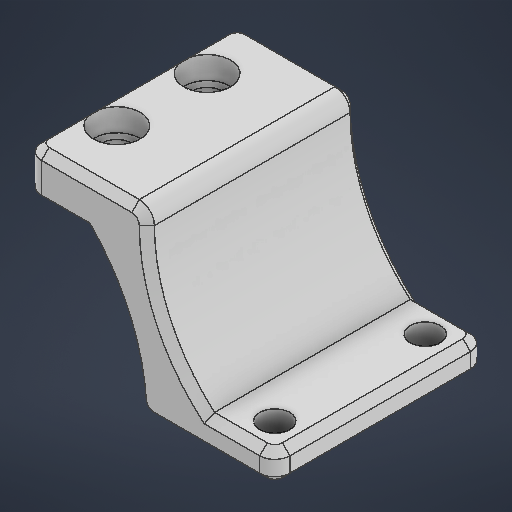
# Autodesk Inventor part: rali-x support
Saved by Autodesk Inventor 2026.2 (Build 302298010, 298A)
## iProperties
Created: 2026-04-26
Part Number: rali-x support
Material: 일반
Document SubType Name: Modeling
Designer: work
Density: 1 g/cm^3
Appearance: 기본값
Author: work
Autodesk Inventor part; units mm, degrees
ref_plane "YZ Plane" through (0, 0, 0) normal (1, 0, 0) x (0, 1, 0)
sketch "스케치1" plane through (0, 0, 0) normal (1, 0, 0) x (0, 1, 0)
  line L0 (0, 0) -> (67.5, 0)
  line L1 (54, 10) -> (54, -10)
  line L2 (67.5, 6) -> (67.5, -6)
  point P0 (54, 0)
  dimension "d0" = 67.5
  dimension "d1" = 54
  dimension "d2" = 20
  dimension "d3" = 12
  constraints: 6 end point, 2 midpoint, 2 vertical, 1 horizontal, 1 point on line
  measures "d0" distance of L0.start L0.end
  measures "d1" distance of L0.start point (54, 0)
  measures "d2" distance of L1.start L1.end
  measures "d3" distance of L2.start L2.end
ref_plane "작업 평면1" through (0, 67.5, 0) normal (0, 1, 0) x (-1, 0, 0)
sketch "스케치2" plane through (0, 67.5, 0) normal (0, 1, 0) x (-1, 0, 0)
  line L0 (0, 6) -> (0, -6) construction
  circle A0 centre (0, 6) radius 2
  circle A1 centre (0, -6) radius 2
  line L1 (4, 10) -> (-12, 10)
  line L2 (-12, 10) -> (-12, -10)
  line L3 (-12, -10) -> (4, -10)
  line L4 (4, -10) -> (4, 10)
  line L5 (4, 14) -> (-12, 14)
  line L6 (-12, 14) -> (-12, -14)
  line L7 (-12, -14) -> (4, -14)
  line L8 (4, -14) -> (4, 14)
  point P0 (0, 0)
  point P1 (-4, 10)
  point P2 (4, 0)
  point P3 (-12, 0)
  point P4 (4, -10)
  dimension "d5" = 12
  dimension "d6" = 4
  dimension "d7" = 4
  dimension "d8" = 4
  dimension "d9" = 4
  dimension "d10" = 4
  dimension "d11" = 12
  dimension "d26" = 28
  constraints: 18 end point, 6 midpoint, 4 parallel, 2 centre point, 2 coincident, 2 horizontal, 2 perpendicular, 1 vertical
  measures "d5" distance of L0.start L0.end
  measures "d6" diameter of A0
  measures "d7" diameter of A1
  measures "d8" horizontal distance of point (-4, 10) L0.start
  measures "d9" distance from line of L3 L0.end
  measures "d10" distance from line of L4 L0.end
  measures "d11" distance from line of L2 L0.end
  measures "d26" distance between parallel lines of L7 L5
extrude "돌출1" add sketch "스케치2" along normal blind 6
ref_plane "작업 평면2" through (0, 54, 0) normal (0, 1, 0) x (-1, 0, 0)
sketch "스케치3" plane through (0, 54, 0) normal (0, 1, 0) x (-1, 0, 0)
  line L0 (0, 0) -> (-25, 0)
  line L1 (-25, 10) -> (-25, -10) construction
  circle A0 centre (-25, 10) radius 2
  circle A1 centre (-25, -10) radius 2
  line L2 (-29, 14) -> (-21, 14)
  line L3 (-21, 14) -> (-21, -14)
  line L4 (-21, -14) -> (-29, -14)
  line L5 (-29, -14) -> (-29, 14)
  line L6 (-29, 14) -> (-21, -14) construction
  line L7 (-21, 14) -> (-29, -14) construction
  line L8 (-21, 14) -> (-11, 14)
  line L9 (-11, 14) -> (-11, -14)
  line L10 (-11, -14) -> (-21, -14)
  line L11 (-21, -14) -> (-21, 14)
  point P0 (-25, -14)
  dimension "d15" = 20
  dimension "d16" = 25
  dimension "d17" = 4
  dimension "d18" = 4
  dimension "d19" = 4
  dimension "d20" = 4
  dimension "d23" = 10
  constraints: 24 end point, 4 midpoint, 4 parallel, 3 horizontal, 2 centre point, 2 coincident, 2 perpendicular, 1 point on line, 1 vertical
  measures "d15" distance of L1.start L1.end
  measures "d16" distance of L0.start L0.end
  measures "d17" diameter of A0
  measures "d18" diameter of A1
  measures "d19" distance from line of L3 L1.end
  measures "d20" distance of point (-25, -14) L1.end
  measures "d23" distance between parallel lines of L3 L9
extrude "돌출2" add sketch "스케치3" against normal blind 4
sketch "스케치5" plane through (11, 54, 14) normal (0, 0, 1) x (1, 0, 0)
  line L0 (18, -4) -> (0, -4) projected
  line L1 (1, 13.5) -> (-15, 13.5) projected
  arc A0 (0, -4) -> (-7, 13.5) centre (-25.375, -4) ccw
  line L2 (0, 0) -> (0, -4) projected
  line L3 (-15, 13.5) -> (1, 13.5) projected
  line L4 (1, 13.5) -> (1, 17.5) projected
  line L5 (-15, 17.5) -> (1, 17.5) projected
  line L6 (-15, 13.5) -> (-15, 17.5) projected
  line L7 (0, 0) -> (18, 0) projected
  line L8 (0, 0) -> (0, -4) projected
  line L9 (18, -4) -> (0, -4) projected
  line L10 (18, 0) -> (18, -4) projected
  arc A1 (1, 17.5) -> (9, 0) centre (24.1406, 17.5) ccw
  line L11 (-7, 13.5) -> (-7, 17.5)
  line L12 (9, 0) -> (9, -4)
  point P0 (-11, -54)
  point P1 (-7, 13.5)
  constraints: 4 end point, 4 midpoint, 4 point on circle, 2 centre point, 2 tangent, 1 perpendicular
extrude "돌출3" add sketch "스케치5" against normal up to surface (28 mm away) contours L0 L2 L7 L12 | A0 L1 L4 A1 L7 L2 | L11 L5 L4 L1
fillet "모깎기1" radius 2 6 edges at (12, 73.5, 0) (11, 50, 0) (-4, 70.5, 14) (29, 52, 14) (29, 52, -14) (-4, 70.5, -14)
chamfer "모따기1" distance 1 angle 45 30 edges at (14.0948, 61.8791, 14) (12, 71.5001, 14) (11.4142, 72.9142, 14) (4, 73.5, 14) (-3.4142, 73.5, 13.4142) (-4, 73.5, 0) (-3.4142, 73.5, -13.4142) (4, 73.5, -14) (12, 71.5001, -14) (11.4142, 72.9142, -14) (14.0948, 61.8791, -14) (8.8249, 60.2789, 14) (11.5652, 50.535, 14) (19.9634, 50, 14) (28.4142, 50, 13.4142) (29, 50, 0) (28.4142, 50, -13.4142) (19.9634, 50, -14) (11.5652, 50.535, -14) (8.8249, 60.2789, -14) (23.5, 54, 14) (28.4142, 54, 13.4142) (29, 54, 0) (28.4142, 54, -13.4142) (23.5, 54, -14) (0.9999, 67.5, -14) (-3.4142, 67.5, -13.4142) (-4, 67.5, 0) (-3.4142, 67.5, 13.4142) (1, 67.5, 14)
sketch "스케치6" plane through (0, 73.5, 0) normal (0, 1, 0) x (1, 0, 0)
  circle A0 centre (0, 6) radius 2 projected
  circle A1 centre (0, -6) radius 2 projected
  line L0 (-2, 13) -> (10, 13) projected
  arc A2 (-2, 13) -> (-3, 12) centre (-2, 12) ccw projected
  line L1 (-3, -12) -> (-3, 12) projected
  arc A3 (-3, -12) -> (-2, -13) centre (-2, -12) ccw projected
  line L2 (10, -13) -> (-2, -13) projected
  line L3 (10, 13) -> (10, -13) projected
  point P0 (0, 0)
  constraints: 2 coincident
hole "구멍1" at (0, 73.5, -6) at (0, 73.5, 6) direction (0, -1, 0) diameter 4 end through all counterbore diameter 6.2 counterbore depth 3
equation "\"d24\" = d3"
